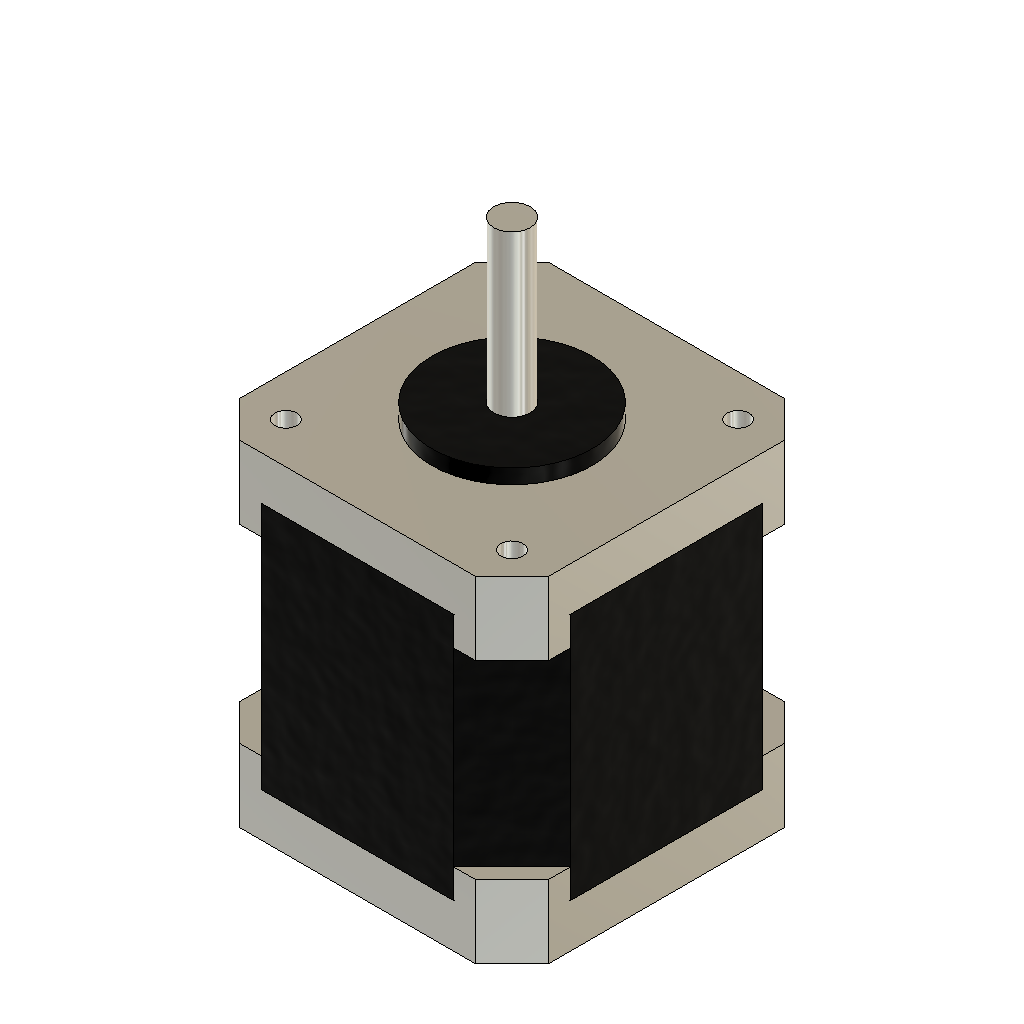
NEMA17 Motor (Autodesk Fusion 360 design; units mm, degrees)
Autodesk Fusion 360 part; units mm, degrees
sketch "Sketch1" plane through (0, 0, 0) normal (0, 0, 1) x (1, 0, 0)
  line L0 (21.15, -21.15) -> (-21.15, -21.15)
  line L1 (-21.15, -21.15) -> (-21.15, 21.15)
  line L2 (-21.15, 21.15) -> (21.15, 21.15)
  line L3 (21.15, 21.15) -> (21.15, -21.15)
  line L4 (21.15, -21.15) -> (-21.15, 21.15) construction
  line L5 (-21.15, -21.15) -> (21.15, 21.15) construction
  circle A0 centre (0, 0) radius 11
  circle A1 centre (0, 0) radius 2.5
  line L6 (15.5, -15.5) -> (-15.5, -15.5) construction
  line L7 (-15.5, -15.5) -> (-15.5, 15.5) construction
  line L8 (-15.5, 15.5) -> (15.5, 15.5) construction
  line L9 (15.5, 15.5) -> (15.5, -15.5) construction
  line L10 (15.5, -15.5) -> (-15.5, 15.5) construction
  line L11 (-15.5, -15.5) -> (15.5, 15.5) construction
  circle A2 centre (-15.5, 15.5) radius 1.5
  circle A3 centre (-15.5, -15.5) radius 1.5
  circle A4 centre (15.5, -15.5) radius 1.5
  circle A5 centre (15.5, 15.5) radius 1.5
  dimension "d1" = 42.3
  dimension "d2" = 22
  dimension "d3" = 5
  dimension "d4" = 31
  dimension "d5" = 31
  dimension "d6" = 3
  dimension "d8" = 360
  constraint horizontal L0
  constraint perpendicular L0 L1
  constraint parallel L0 L2
  constraint parallel L1 L3
  constraint coincident L4 A0.centre
  constraint coincident L5 A0.centre
  constraint coincident A0.centre A1.centre
  constraint equal L1 L2
  constraint horizontal L6
  constraint perpendicular L6 L7
  constraint parallel L6 L8
  constraint parallel L7 L9
  constraint coincident L10 A0.centre
  constraint coincident L11 A0.centre
  constraint coincident L7 L8.start
  constraint coincident L8 L7.end
  measures "d1" distance of L1.end L2.end
  measures "d2" diameter of A0
  measures "d3" diameter of A1
  measures "d4" distance of L7.end L8.end
  measures "d5" distance of L6.start L8.end
  measures "d6" diameter of A2
extrude "Extrude1" add sketch "Sketch1" against normal blind 10 contours L0 L1 L2 L3 | A0 | A1 makes body 1
chamfer "Chamfer1" distance 5 angle 45 4 edges at (21.15, -21.15, -5) (-21.15, -21.15, -5) (21.15, 21.15, -5) (-21.15, 21.15, -5) tangent chain off on bodies 1
extrude "Extrude2" add sketch "Sketch1" along normal blind 2 separate body contours A0 makes body 2
extrude "Extrude3" add sketch "Sketch1" along normal blind 24 separate body contours A1 makes body 3
sketch "Sketch2" plane through (0, 0, -10) normal (0, 0, -1) x (1, 0, 0)
  line L0 (-21.15, -16.15) -> (-16.15, -21.15) construction
  line L1 (-16.15, -21.15) -> (16.15, -21.15) construction
  line L2 (16.15, -21.15) -> (21.15, -16.15) construction
  line L3 (21.15, -16.15) -> (21.15, 16.15) construction
  line L4 (21.15, 16.15) -> (16.15, 21.15) construction
  line L5 (16.15, 21.15) -> (-16.15, 21.15) construction
  line L6 (-16.15, 21.15) -> (-21.15, 16.15) construction
  line L7 (-21.15, 16.15) -> (-21.15, -16.15) construction
  circle A0 centre (-15.5, 15.5) radius 1.5
  circle A1 centre (-15.5, -15.5) radius 1.5
  circle A2 centre (15.5, 15.5) radius 1.5
  circle A3 centre (15.5, -15.5) radius 1.5
  line L8 (21.15, -21.15) -> (-21.15, -21.15)
  line L9 (-21.15, -21.15) -> (-21.15, 21.15)
  line L10 (-21.15, 21.15) -> (21.15, 21.15)
  line L11 (21.15, 21.15) -> (21.15, -21.15)
  constraint horizontal L8
  constraint vertical L9
  constraint horizontal L10
  constraint vertical L11
  constraint collinear L1 L8
  constraint collinear L5 L10
  constraint collinear L7 L9
  constraint collinear L3 L11
extrude "Extrude4" add sketch "Sketch2" along normal blind 25 separate body makes body 4
chamfer "Chamfer2" distance 8 angle 45 4 edges at (21.15, -21.15, -22.5) (21.15, 21.15, -22.5) (-21.15, -21.15, -22.5) (-21.15, 21.15, -22.5) tangent chain off on bodies 4
extrude "Extrude5" add 1 faces at (-4.8001, 4.8266, -10) along direction (0, 0, 1) blind 4 on bodies 4 bodies 4
extrude "Extrude6" add 1 faces at (-4.8001, 4.8266, -35) along direction (0, 0, -1) blind 5 on bodies 4 bodies 4
combine "Combine2" operation cut target body 1 tool bodies 4 keep tools
ref_plane "WorkPlane1" through (0, 0, -23) normal (0, 0, 1) x (-1, 0, 0)
mirror "Mirror1" about plane through (0, 0, -23) normal (0, 0, 1) of bodies 1 makes body 5
combine "Combine3" operation add target body 1 tool bodies 2 3
